Autodesk Fusion 360 part; units mm, degrees
(part 2 of 2)
sketch "Bottom cover snap 55 outline" plane through (52.5, 0, 0) normal (1, 0, 0) x (0, 0, -1) in component "02 Snap-on front cover - PRINT"
  line L0 (-71.75, -14.2) -> (-72.95, -14.2)
  line L1 (-72.95, -14.2) -> (-72.95, -1.8)
  line L2 (-72.95, -1.8) -> (-71.75, -1.8)
  line L3 (-71.75, -1.8) -> (-70.8, -3.2)
  line L4 (-70.8, -3.2) -> (-70.8, -4)
  line L5 (-70.8, -4) -> (-71.75, -4)
  line L6 (-71.75, -4) -> (-71.75, -14.2)
extrude "Bottom cover snap 55" add sketch "Bottom cover snap 55 outline" along normal blind 5 bodies 21 in component "02 Snap-on front cover - PRINT"
ref_plane "WorkPlane21" through (52.5, 0, 0) normal (1, 0, 0) x (0, 1, 0) in component "02 Snap-on front cover - PRINT"
sketch "Top cover snap 55 outline" plane through (52.5, 0, 0) normal (1, 0, 0) x (0, 0, -1) in component "02 Snap-on front cover - PRINT"
  line L0 (-163.45, -14.2) -> (-164.25, -14.2)
  line L1 (-164.25, -14.2) -> (-164.25, -9)
  line L2 (-164.25, -9) -> (-165.2, -9)
  line L3 (-165.2, -9) -> (-165.2, -8.2)
  line L4 (-165.2, -8.2) -> (-164.25, -6.8)
  line L5 (-164.25, -6.8) -> (-163.45, -6.8)
  line L6 (-163.45, -6.8) -> (-163.45, -14.2)
extrude "Top cover snap 55" add sketch "Top cover snap 55 outline" along normal blind 5 bodies 21 in component "02 Snap-on front cover - PRINT"
ref_plane "WorkPlane22" through (156.5, 0, 0) normal (1, 0, 0) x (0, 1, 0) in component "02 Snap-on front cover - PRINT"
sketch "Bottom cover snap 159 outline" plane through (156.5, 0, 0) normal (1, 0, 0) x (0, 0, -1) in component "02 Snap-on front cover - PRINT"
  line L0 (-71.75, -14.2) -> (-72.95, -14.2)
  line L1 (-72.95, -14.2) -> (-72.95, -1.8)
  line L2 (-72.95, -1.8) -> (-71.75, -1.8)
  line L3 (-71.75, -1.8) -> (-70.8, -3.2)
  line L4 (-70.8, -3.2) -> (-70.8, -4)
  line L5 (-70.8, -4) -> (-71.75, -4)
  line L6 (-71.75, -4) -> (-71.75, -14.2)
extrude "Bottom cover snap 159" add sketch "Bottom cover snap 159 outline" along normal blind 5 bodies 21 in component "02 Snap-on front cover - PRINT"
ref_plane "WorkPlane23" through (156.5, 0, 0) normal (1, 0, 0) x (0, 1, 0) in component "02 Snap-on front cover - PRINT"
sketch "Top cover snap 159 outline" plane through (156.5, 0, 0) normal (1, 0, 0) x (0, 0, -1) in component "02 Snap-on front cover - PRINT"
  line L0 (-163.45, -14.2) -> (-164.25, -14.2)
  line L1 (-164.25, -14.2) -> (-164.25, -9)
  line L2 (-164.25, -9) -> (-165.2, -9)
  line L3 (-165.2, -9) -> (-165.2, -8.2)
  line L4 (-165.2, -8.2) -> (-164.25, -6.8)
  line L5 (-164.25, -6.8) -> (-163.45, -6.8)
  line L6 (-163.45, -6.8) -> (-163.45, -14.2)
extrude "Top cover snap 159" add sketch "Top cover snap 159 outline" along normal blind 5 bodies 21 in component "02 Snap-on front cover - PRINT"
ref_plane "WorkPlane1" through (0, 0, -29) normal (0, 0, 1) x (1, 0, 0) in component "03 Snap-on downward camera guard - PRINT"
sketch "Camera guard shell outline" plane through (0, 0, -29) normal (0, 0, 1) x (1, 0, 0) in component "03 Snap-on downward camera guard - PRINT"
  line L0 (85.2, -26.45) -> (128.8, -26.45)
  line L1 (130.8, -24.45) -> (130.8, 19.15)
  line L2 (128.8, 21.15) -> (85.2, 21.15)
  line L3 (83.2, 19.15) -> (83.2, -24.45)
  arc A0 (128.8, -26.45) -> (130.8, -24.45) centre (128.8, -24.45) ccw
  arc A1 (130.8, 19.15) -> (128.8, 21.15) centre (128.8, 19.15) ccw
  arc A2 (85.2, 21.15) -> (83.2, 19.15) centre (85.2, 19.15) ccw
  arc A3 (83.2, -24.45) -> (85.2, -26.45) centre (85.2, -24.45) ccw
extrude "Camera guard shell" add sketch "Camera guard shell outline" along normal blind 18.6 separate body makes body 22 in component "03 Snap-on downward camera guard - PRINT"
ref_plane "WorkPlane2" through (0, 0, -26.6) normal (0, 0, 1) x (1, 0, 0) in component "03 Snap-on downward camera guard - PRINT"
sketch "Camera cavity outline" plane through (0, 0, -26.6) normal (0, 0, 1) x (1, 0, 0) in component "03 Snap-on downward camera guard - PRINT"
  line L0 (85.6, -24.05) -> (128.4, -24.05)
  line L1 (128.4, -24.05) -> (128.4, 18.75)
  line L2 (128.4, 18.75) -> (85.6, 18.75)
  line L3 (85.6, 18.75) -> (85.6, -24.05)
extrude "Camera cavity" cut sketch "Camera cavity outline" along normal blind 16.3 bodies 22 in component "03 Snap-on downward camera guard - PRINT"
ref_plane "WorkPlane3" through (0, 0, -29.1) normal (0, 0, 1) x (1, 0, 0) in component "03 Snap-on downward camera guard - PRINT"
sketch "Fisheye aperture layout" plane through (0, 0, -29.1) normal (0, 0, 1) x (1, 0, 0) in component "03 Snap-on downward camera guard - PRINT"
  circle A0 centre (107, 0) radius 11
extrude "Fisheye aperture" cut sketch "Fisheye aperture layout" along normal blind 2.6 bodies 22 in component "03 Snap-on downward camera guard - PRINT"
ref_plane "WorkPlane4" through (0, 0, -19) normal (0, 0, 1) x (1, 0, 0) in component "03 Snap-on downward camera guard - PRINT"
sketch "Ribbon exit outline" plane through (0, 0, -19) normal (0, 0, 1) x (1, 0, 0) in component "03 Snap-on downward camera guard - PRINT"
  line L0 (98, -26.6) -> (116, -26.6)
  line L1 (116, -26.6) -> (116, -23.9)
  line L2 (116, -23.9) -> (98, -23.9)
  line L3 (98, -23.9) -> (98, -26.6)
extrude "Ribbon exit" cut sketch "Ribbon exit outline" along normal blind 8.7 bodies 22 in component "03 Snap-on downward camera guard - PRINT"
ref_plane "WorkPlane5" through (0, 0, -25) normal (0, 0, 1) x (1, 0, 0) in component "03 Snap-on downward camera guard - PRINT"
sketch "L flexible tongue clearance outline" plane through (0, 0, -25) normal (0, 0, 1) x (1, 0, 0) in component "03 Snap-on downward camera guard - PRINT"
  line L0 (83.1, -3.6) -> (85.7, -3.6)
  line L1 (85.7, -3.6) -> (85.7, 3.6)
  line L2 (85.7, 3.6) -> (83.1, 3.6)
  line L3 (83.1, 3.6) -> (83.1, -3.6)
extrude "L flexible tongue clearance" cut sketch "L flexible tongue clearance outline" along normal blind 14.7 bodies 22 in component "03 Snap-on downward camera guard - PRINT"
ref_plane "WorkPlane6" through (0, 0, -25) normal (0, 0, 1) x (1, 0, 0) in component "03 Snap-on downward camera guard - PRINT"
sketch "R flexible tongue clearance outline" plane through (0, 0, -25) normal (0, 0, 1) x (1, 0, 0) in component "03 Snap-on downward camera guard - PRINT"
  line L0 (128.3, -3.6) -> (130.9, -3.6)
  line L1 (130.9, -3.6) -> (130.9, 3.6)
  line L2 (130.9, 3.6) -> (128.3, 3.6)
  line L3 (128.3, 3.6) -> (128.3, -3.6)
extrude "R flexible tongue clearance" cut sketch "R flexible tongue clearance outline" along normal blind 14.7 bodies 22 in component "03 Snap-on downward camera guard - PRINT"
ref_plane "WorkPlane7" through (0, -3, 0) normal (0, 1, 0) x (0, 0, 1) in component "03 Snap-on downward camera guard - PRINT"
sketch "Left releasable camera snap outline" plane through (0, -3, 0) normal (0, 1, 0) x (1, 0, 0) in component "03 Snap-on downward camera guard - PRINT"
  line L0 (84.4, 25) -> (85.6, 25)
  line L1 (85.6, 25) -> (85.6, 8.5)
  line L2 (85.6, 8.5) -> (86.7, 8.5)
  line L3 (86.7, 8.5) -> (86.7, 7)
  line L4 (86.7, 7) -> (85.6, 5.4)
  line L5 (85.6, 5.4) -> (84.4, 5.4)
  line L6 (84.4, 5.4) -> (84.4, 25)
extrude "Left releasable camera snap" add sketch "Left releasable camera snap outline" along normal blind 6 bodies 22 in component "03 Snap-on downward camera guard - PRINT"
ref_plane "WorkPlane8" through (0, -3, 0) normal (0, 1, 0) x (0, 0, 1) in component "03 Snap-on downward camera guard - PRINT"
sketch "Right releasable camera snap outline" plane through (0, -3, 0) normal (0, 1, 0) x (1, 0, 0) in component "03 Snap-on downward camera guard - PRINT"
  line L0 (129.6, 25) -> (128.4, 25)
  line L1 (128.4, 25) -> (128.4, 8.5)
  line L2 (128.4, 8.5) -> (127.3, 8.5)
  line L3 (127.3, 8.5) -> (127.3, 7)
  line L4 (127.3, 7) -> (128.4, 5.4)
  line L5 (128.4, 5.4) -> (129.6, 5.4)
  line L6 (129.6, 5.4) -> (129.6, 25)
extrude "Right releasable camera snap" add sketch "Right releasable camera snap outline" along normal blind 6 bodies 22 in component "03 Snap-on downward camera guard - PRINT"
sketch "Insert coupon base outline" plane through (0, 0, 0) normal (0, 0, 1) x (1, 0, 0) in component "08 Heat-set test coupon - TEST PRINT"
  line L0 (245, 0) -> (280, 0)
  line L1 (280, 0) -> (280, 16)
  line L2 (280, 16) -> (245, 16)
  line L3 (245, 16) -> (245, 0)
extrude "Insert coupon base" add sketch "Insert coupon base outline" along normal blind 2 separate body makes body 23 in component "08 Heat-set test coupon - TEST PRINT"
ref_plane "WorkPlane1" through (0, 0, 2) normal (0, 0, 1) x (1, 0, 0) in component "08 Heat-set test coupon - TEST PRINT"
sketch "M2 coupon boss layout" plane through (0, 0, 2) normal (0, 0, 1) x (1, 0, 0) in component "08 Heat-set test coupon - TEST PRINT"
  circle A0 centre (253, 8) radius 3.2
extrude "M2 coupon boss" add sketch "M2 coupon boss layout" along normal blind 5 bodies 23 in component "08 Heat-set test coupon - TEST PRINT"
ref_plane "WorkPlane2" through (0, 0, 7) normal (0, 0, 1) x (1, 0, 0) in component "08 Heat-set test coupon - TEST PRINT"
sketch "M2 coupon 3.2 x 4 hole layout" plane through (0, 0, 7) normal (0, 0, 1) x (1, 0, 0) in component "08 Heat-set test coupon - TEST PRINT"
  circle A0 centre (253, 8) radius 1.6
extrude "M2 coupon 3.2 x 4 hole" cut sketch "M2 coupon 3.2 x 4 hole layout" against normal blind 4 bodies 23 in component "08 Heat-set test coupon - TEST PRINT"
ref_plane "WorkPlane3" through (0, 0, 2) normal (0, 0, 1) x (1, 0, 0) in component "08 Heat-set test coupon - TEST PRINT"
sketch "M2.5 coupon boss layout" plane through (0, 0, 2) normal (0, 0, 1) x (1, 0, 0) in component "08 Heat-set test coupon - TEST PRINT"
  circle A0 centre (271, 8) radius 4
extrude "M2.5 coupon boss" add sketch "M2.5 coupon boss layout" along normal blind 6 bodies 23 in component "08 Heat-set test coupon - TEST PRINT"
ref_plane "WorkPlane4" through (0, 0, 8) normal (0, 0, 1) x (1, 0, 0) in component "08 Heat-set test coupon - TEST PRINT"
sketch "M2.5 coupon 4 x 5 hole layout" plane through (0, 0, 8) normal (0, 0, 1) x (1, 0, 0) in component "08 Heat-set test coupon - TEST PRINT"
  circle A0 centre (271, 8) radius 2
extrude "M2.5 coupon 4 x 5 hole" cut sketch "M2.5 coupon 4 x 5 hole layout" against normal blind 5 bodies 23 in component "08 Heat-set test coupon - TEST PRINT"
component "REFERENCE - INIU P51L-E2 115 x 73 x 29 mm" placed x (-1, 0, 0) y (0, 0, 1) z (0, 1, 0) at (129, -14, 68.5)
component "REFERENCE - Raspberry Pi4 rotated ports" placed x (0, 0, -1) y (1, 0, 0) z (0, -1, 0) at (131, 60, 166)
component "REFERENCE - Waveshare RPi Camera G PCB and lens" placed x (-1, 0, 0) y (0, 1, 0) z (0, 0, -1) at (126, -21.65, -8)
component "REFERENCE - six mount pads - compressed" placed x (1, 0, 0) y (0, 1, 0) z (0, 0, 1) at (0, 0, 0)
component "REFERENCE - upward-stepped frame - back wall assumed" placed x (1, 0, 0) y (0, 1, 0) z (0, 0, 1) at (0, 0, 0)
component "07 Upward-step fit gauge PRINT FIRST - PRINT" placed x (1, 0, 0) y (0, 1, 0) z (0, 0, 1) at (0, 0, 0)
component "01 Integral case mount and camera holder - PRINT" placed x (1, 0, 0) y (0, 1, 0) z (0, 0, 1) at (0, 0, 0)
component "02 Snap-on front cover - PRINT" placed x (1, 0, 0) y (0, 1, 0) z (0, 0, 1) at (0, 0, 0)
component "03 Snap-on downward camera guard - PRINT" placed x (1, 0, 0) y (0, 1, 0) z (0, 0, 1) at (0, 0, 0)
component "08 Heat-set test coupon - TEST PRINT" placed x (1, 0, 0) y (0, 1, 0) z (0, 0, 1) at (0, 0, 0)
equation "wall = 2.4 mm" comment "Printed shell wall and tray thickness"
equation "battery_tray_height = 37 mm" comment "Battery chamber outside height"
equation "upper_height = 32 mm" comment "Pi chamber height above battery tray"
equation "lid_thickness = 2.4 mm" comment "Removable lid"
equation "pi_standoff_height = 5 mm" comment "Pi underside clearance"
equation "pad_recess_depth = 0.8 mm" comment "Use 3 mm rubber pads; 2.2 mm projects below case"
equation "camera_carrier_thickness = 3 mm" comment "Camera backplate"
equation "camera_standoff_height = 2.5 mm" comment "Clearance under camera PCB"
equation "camera_lens_opening = 22 mm" comment "Generous opening; check actual lens barrel before final print"
equation "camera_cap_height = 17 mm" comment "Cap height above carrier; lens must project beyond the front"
equation "insert_M2_hole = 3.2 mm" comment "CNC Kitchen M2 x 3: D1=3.6, pilot=3.2, blind depth >=4"
equation "insert_M25_hole = 4 mm" comment "CNC Kitchen M2.5 x 4: D1=4.6, pilot=4, blind depth >=5"
equation "snap_clearance = 0.35 mm" comment "Nominal printed locator clearance; fit-test before assembly"
named bodies: "INIU envelope - check supplied cable position", "Pi PCB 85 x 56 x 1.6", "USB3", "USB2", "Ethernet", "USB-C", "HDMI0", "HDMI1", "Audio", "Camera PCB 25 x 24", "left lower-ledge pad - 20 x 10 x 3", "left upper-ledge pad - 20 x 9 x 3", "left underside retaining pad - 16 x 14 x 3", "right lower-ledge pad - 20 x 10 x 3", "right upper-ledge pad - 20 x 9 x 3", "right underside retaining pad - 16 x 14 x 3", "Open-front case", "Front cover", "Camera guard shell", "Insert coupon base"
